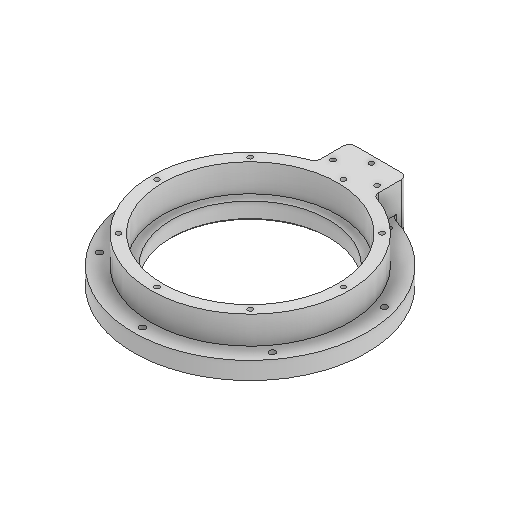
# Autodesk Inventor part: 3DP_PLA_A_Axis_Bearing_Base
Saved by Autodesk Inventor 2027 (Build 310192060, 192F)
## iProperties
Created: 2026-01-06
Part Number: 3DP_PLA_A_Axis_Bearing_Base
Material: Generic
Document SubType Name: Modeling
Designer: User
Density: 1 g/cm^3
Appearance: Default
Author: User
Autodesk Inventor part; units mm, degrees
ref_plane "YZ Plane" through (0, 0, 0) normal (1, 0, 0) x (0, 1, 0)
ref_plane "XZ Plane" through (0, 0, 0) normal (0, 1, 0) x (-1, 0, 0)
ref_plane "XY Plane" through (0, 0, 0) normal (0, 0, 1) x (1, 0, 0)
sketch "Sketch1" plane through (0, 0, 0) normal (0, 1, 0) x (-1, 0, 0)
  circle A0 centre (0, 0) radius 75.1
  circle A1 centre (0, 0) radius 85.1
  circle A2 centre (0, 0) radius 67.5
  circle A3 centre (0, 0) radius 100.1
  line L0 (25, -81.345) -> (25, -110)
  line L1 (25, -110) -> (-25, -110)
  line L2 (-25, -110) -> (-25, -81.345)
  point P0 (25, -96.9279)
  point P1 (-25, -96.9279)
  point P2 (0, -100)
  point P3 (0, -104)
  point P4 (19, -90)
  point P5 (-19, -90)
  dimension "d0" = 150.2
  dimension "d1" = 10
  dimension "d2" = 135
  dimension "d3" = 15
  dimension "d32" = 25
  dimension "d33" = 25
  dimension "d34" = 110
  dimension "d39" = 20
  dimension "d40" = 6
  dimension "d41" = 6
  dimension "d42" = 25
  dimension "d43" = 6
  constraints: 6 end point, 4 centre point, 2 coincident, 2 perpendicular, 2 point on circle, 1 horizontal alignment, 1 vertical
  measures "d0" diameter of A0
  measures "d1" radial gap between concentric circles of A0 A1
  measures "d2" diameter of A2
  measures "d3" radial gap between concentric circles of A1 A3
  measures "d32" distance from line of point (0, 0) L0
  measures "d33" distance from line of point (0, 0) L2
  measures "d34" distance from line of point (0, 0) L1
  measures "d39" distance from line of L1 point (19, -90)
  measures "d40" distance from line of L2 point (-19, -90)
  measures "d41" distance from line of L0 point (19, -90)
  measures "d42" distance from line of L2 point (0, -104)
  measures "d43" distance from line of L1 point (0, -104)
extrude "Extrusion1" add sketch "Sketch1" against normal blind 15 contours A0 | A1 | A1 L2 A3 L0 | A1 L0 A3 L2
extrude "Extrusion2" add sketch "Sketch1" along normal blind 23.8 contours A1
sketch "Sketch2" plane through (0, 23.8, 0) normal (0, 1, 0) x (1, 0, 0)
  circle A0 centre (0, 0) radius 85.1 projected
  circle A1 centre (0, 0) radius 75.1 projected
  point P0 (0, 80)
  point P1 (-56.5685, 56.5685)
  point P2 (-80, 0)
  point P3 (-56.5685, -56.5685)
  point P4 (0, -80)
  point P5 (56.5685, -56.5685)
  point P6 (80, 0)
  point P7 (56.5685, 56.5685)
  dimension "d8" = 150.2
  dimension "d9" = 170.2
  dimension "d10" = 80
  dimension "d13" = 360
  constraints: 9 other
  measures "d8" diameter of A1
  measures "d9" diameter of A0
  measures "d10" distance of point (0, 0) point (0, 80)
hole "Hole1" at (0, 23.8, -80) at (-56.5685, 23.8, -56.5685) at (-80, 23.8, 0) at (-56.5685, 23.8, 56.5685) at (0, 23.8, 80) at (56.5685, 23.8, 56.5685) at (80, 23.8, 0) at (56.5685, 23.8, -56.5685) direction (0, -1, 0) diameter 4.2 end through all
sketch "Sketch3" plane through (0, -15, 0) normal (0, -1, 0) x (1, 0, 0)
  circle A0 centre (56.5685, -56.5685) radius 2.1 projected
  circle A1 centre (80, 0) radius 2.1 projected
  circle A2 centre (56.5685, 56.5685) radius 2.1 projected
  circle A3 centre (0, 80) radius 2.1 projected
  circle A4 centre (-56.5685, 56.5685) radius 2.1 projected
  circle A5 centre (-80, 0) radius 2.1 projected
  circle A6 centre (-56.5685, -56.5685) radius 2.1 projected
  circle A7 centre (0, -80) radius 2.1 projected
  circle A8 centre (0, 0) radius 100.1 projected
  circle A9 centre (0, 0) radius 67.5 projected
  line L0 (2.1651, 83.75) -> (4.3301, 80)
  line L1 (4.3301, 80) -> (2.1651, 76.25)
  line L2 (2.1651, 76.25) -> (-2.1651, 76.25)
  line L3 (-2.1651, 76.25) -> (-4.3301, 80)
  line L4 (-4.3301, 80) -> (-2.1651, 83.75)
  line L5 (-2.1651, 83.75) -> (2.1651, 83.75)
  line L6 (-52.386, 55.4478) -> (-55.4478, 52.386)
  line L7 (-55.4478, 52.386) -> (-59.6304, 53.5067)
  line L8 (-59.6304, 53.5067) -> (-60.7511, 57.6893)
  line L9 (-53.5067, 59.6304) -> (-52.386, 55.4478)
  line L10 (-60.7511, 57.6893) -> (-57.6893, 60.7511)
  line L11 (-57.6893, 60.7511) -> (-53.5067, 59.6304)
  line L12 (-76.25, 2.1651) -> (-76.25, -2.1651)
  line L13 (-76.25, -2.1651) -> (-80, -4.3301)
  line L14 (-80, -4.3301) -> (-83.75, -2.1651)
  line L15 (-80, 4.3301) -> (-76.25, 2.1651)
  line L16 (-83.75, -2.1651) -> (-83.75, 2.1651)
  line L17 (-83.75, 2.1651) -> (-80, 4.3301)
  line L18 (-55.4478, -52.386) -> (-52.386, -55.4478)
  line L19 (-52.386, -55.4478) -> (-53.5067, -59.6304)
  line L20 (-53.5067, -59.6304) -> (-57.6893, -60.7511)
  line L21 (-59.6304, -53.5067) -> (-55.4478, -52.386)
  line L22 (-57.6893, -60.7511) -> (-60.7511, -57.6893)
  line L23 (-60.7511, -57.6893) -> (-59.6304, -53.5067)
  line L24 (-2.1651, -76.25) -> (2.1651, -76.25)
  line L25 (2.1651, -76.25) -> (4.3301, -80)
  line L26 (4.3301, -80) -> (2.1651, -83.75)
  line L27 (-4.3301, -80) -> (-2.1651, -76.25)
  line L28 (2.1651, -83.75) -> (-2.1651, -83.75)
  line L29 (-2.1651, -83.75) -> (-4.3301, -80)
  line L30 (52.386, -55.4478) -> (55.4478, -52.386)
  line L31 (55.4478, -52.386) -> (59.6304, -53.5067)
  line L32 (59.6304, -53.5067) -> (60.7511, -57.6893)
  line L33 (53.5067, -59.6304) -> (52.386, -55.4478)
  line L34 (60.7511, -57.6893) -> (57.6893, -60.7511)
  line L35 (57.6893, -60.7511) -> (53.5067, -59.6304)
  line L36 (76.25, -2.1651) -> (76.25, 2.1651)
  line L37 (76.25, 2.1651) -> (80, 4.3301)
  line L38 (80, 4.3301) -> (83.75, 2.1651)
  line L39 (80, -4.3301) -> (76.25, -2.1651)
  line L40 (83.75, 2.1651) -> (83.75, -2.1651)
  line L41 (83.75, -2.1651) -> (80, -4.3301)
  line L42 (55.4478, 52.386) -> (52.386, 55.4478)
  line L43 (52.386, 55.4478) -> (53.5067, 59.6304)
  line L44 (53.5067, 59.6304) -> (57.6893, 60.7511)
  line L45 (59.6304, 53.5067) -> (55.4478, 52.386)
  line L46 (57.6893, 60.7511) -> (60.7511, 57.6893)
  line L47 (60.7511, 57.6893) -> (59.6304, 53.5067)
  point P0 (-56.5685, 56.5685)
  point P1 (-56.5685, -56.5685)
  point P2 (56.5685, -56.5685)
  point P3 (80, 0)
  point P4 (56.5685, 56.5685)
  dimension "d22" = 7.5
  dimension "d25" = 360
  constraints: 96 end point, 1 coincident, 118 other
  measures "d22" distance between parallel lines of L2 L5
extrude "Extrusion3" cut sketch "Sketch3" against normal blind 10 contours L0 L1 L2 L3 L4 L5 | L6 L7 L8 L10 L11 L9 | L12 L13 L14 L16 L17 L15 | L18 L19 L20 L22 L23 L21 | L24 L25 L26 L28 L29 L27 | L30 L31 L32 L34 L35 L33 | L36 L37 L38 L40 L41 L39 | L42 L43 L44 L46 L47 L45
chamfer "Chamfer1" distance 2 angle 45 1 edges at (67.5, -15, 0)
extrude "Extrusion4" add sketch "Sketch1" against normal up to surface (15 mm away) contours A3 L0 L1 L2
extrude "Extrusion5" add sketch "Sketch1" along normal up to surface (23.8 mm away) contours A1 L0 A3 L2 | A3 L0 L1 L2 picked at (20.8801, -87.4763)
hole "Hole2" at (0, 0, -104) at (-19, 0, -90) at (19, 0, -90) direction (0, -1, 0) diameter 4.2 end through all both
fillet "Fillet1" radius 5 4 edges at (25, 11.9, -81.345) (25, 4.4, -110) (-25, 11.9, -81.345) (-25, 4.4, -110)
fillet "Fillet2" radius 5 2 edges at (25, -7.5, -96.9279) (-25, -7.5, -96.9279)
sketch "Sketch4" plane through (0, -15, 0) normal (0, -1, 0) x (1, 0, 0)
  circle A0 centre (19, -90) radius 2.1 projected
  circle A1 centre (0, -104) radius 2.1 projected
  circle A2 centre (-19, -90) radius 2.1 projected
  line L0 (22.75, -92.1651) -> (19, -94.3301)
  line L1 (19, -94.3301) -> (15.25, -92.1651)
  line L2 (15.25, -92.1651) -> (15.25, -87.8349)
  line L3 (15.25, -87.8349) -> (19, -85.6699)
  line L4 (19, -85.6699) -> (22.75, -87.8349)
  line L5 (22.75, -87.8349) -> (22.75, -92.1651)
  line L6 (3.75, -106.1651) -> (0, -108.3301)
  line L7 (0, -108.3301) -> (-3.75, -106.1651)
  line L8 (-3.75, -106.1651) -> (-3.75, -101.8349)
  line L9 (-3.75, -101.8349) -> (0, -99.6699)
  line L10 (0, -99.6699) -> (3.75, -101.8349)
  line L11 (3.75, -101.8349) -> (3.75, -106.1651)
  line L12 (-15.25, -92.1651) -> (-19, -94.3301)
  line L13 (-19, -94.3301) -> (-22.75, -92.1651)
  line L14 (-22.75, -92.1651) -> (-22.75, -87.8349)
  line L15 (-22.75, -87.8349) -> (-19, -85.6699)
  line L16 (-19, -85.6699) -> (-15.25, -87.8349)
  line L17 (-15.25, -87.8349) -> (-15.25, -92.1651)
  point P0 (0, 0)
  dimension "d53" = 7.5
  dimension "d54" = 7.5
  dimension "d55" = 7.5
  constraints: 36 end point, 3 coincident, 39 other
  measures "d53" distance between parallel lines of L2 L5
  measures "d54" distance between parallel lines of L8 L11
  measures "d55" distance between parallel lines of L14 L17
extrude "Extrusion6" cut sketch "Sketch4" against normal blind 14
sketch "Sketch5" plane through (0, 0, 0) normal (0, 1, 0) x (1, 0, 0)
  arc A0 (-28.3352, 80.2442) -> (-25, 84.9589) centre (-30, 84.9589) ccw projected
  line L0 (-25, 84.9589) -> (-25, 100.7274) projected
  arc A1 (-28.5728, 95.9354) -> (-25, 100.7274) centre (-30, 100.7274) ccw projected
  arc A2 (-28.5728, 95.9354) -> (28.5728, 95.9354) centre (0, 0) ccw projected
  arc A3 (25, 100.7274) -> (28.5728, 95.9354) centre (30, 100.7274) ccw projected
  line L1 (25, 100.7274) -> (25, 84.9589) projected
  arc A4 (25, 84.9589) -> (28.3352, 80.2442) centre (30, 84.9589) ccw projected
  arc A5 (-28.3352, 80.2442) -> (28.3352, 80.2442) centre (0, 0) ccw projected
  point P0 (0, -92.5)
  dimension "d58" = 92.5
  dimension "d59" = 85.1
  dimension "d60" = 100.1
  measures "d58" distance of point (0, 0) point (0, -92.5)
  measures "d59" radius of A5
  measures "d60" radius of A2
hole "Hole3" at (0, 0, 92.5) direction (0, -1, 0) diameter 5.2 end through all
pattern_circular "Circular Pattern1" count 4 over 160 about axis through (0, 0, 0) along (0, -1, 0) of "Hole3"
pattern_circular "Circular Pattern2" count 4 over 160 about axis through (0, 0, 0) along (0, 1, 0) of "Hole3"
sketch "Sketch6" plane through (-25, -15, -105) normal (-1, 0, 0) x (0, 0, 1)
  line L0 (-5, 38.8) -> (-5, 0) projected
  line L1 (20.0411, 38.8) -> (0, 38.8) projected
  point P0 (105, 15)
  point P1 (8, 32.8)
  dimension "d74" = 6
  dimension "d75" = 13
  measures "d74" distance from line of point (8, 32.8) L1
  measures "d75" distance from line of L0 point (8, 32.8)
hole "Hole4" at (-25, 17.8, -97) direction (1, 0, 0) diameter 5.5 depth 8.5
equation "\"d33\" = d32"
equation "\"d41\" = d40"
equation "\"d54\" = d53"
equation "\"d55\" = d54"
body "Solid1"
